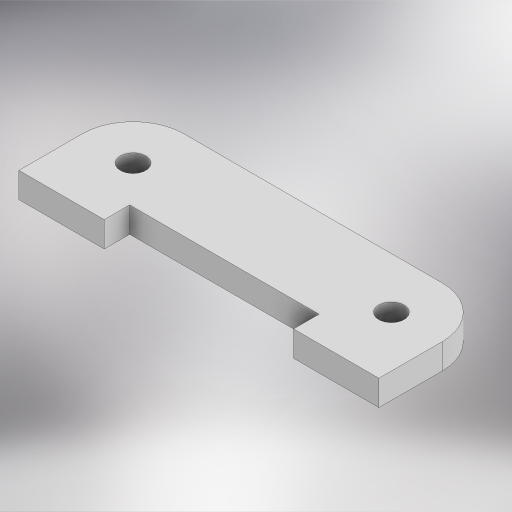
# Autodesk Inventor part: board_holder
Saved by Autodesk Inventor 2023.5 (Build 275446000, 446)
## iProperties
Created: 2026-10-31
Part Number: board_holder
Material: Generic
Document SubType Name: Modeling
Designer: WORKPLUS
Density: 1 g/cm^3
Appearance: Default
Author: WORKPLUS
Autodesk Inventor part; units mm, degrees
ref_plane "YZ Plane" through (0, 0, 0) normal (1, 0, 0) x (0, 1, 0)
ref_plane "XZ Plane" through (0, 0, 0) normal (0, 1, 0) x (-1, 0, 0)
ref_plane "XY Plane" through (0, 0, 0) normal (0, 0, 1) x (1, 0, 0)
sketch "Sketch1" plane through (0, 0, 0) normal (0, 1, 0) x (-1, 0, 0)
  line L0 (35.4, -23.719) -> (35.4, -36.169)
  line L1 (25.4, -46.169) -> (-25.4, -46.169)
  line L2 (-35.4, -36.169) -> (-35.4, -23.719)
  circle A0 centre (25.4, -36.169) radius 2.5
  circle A1 centre (-25.4, -36.169) radius 2.5
  arc A2 (25.4, -46.169) -> (35.4, -36.169) centre (25.4, -36.169) ccw
  arc A3 (-35.4, -36.169) -> (-25.4, -46.169) centre (-25.4, -36.169) ccw
  line L3 (-18.6144, -21.219) -> (-18.6146, -21.219)
  line L4 (-18.6146, -23.719) -> (-18.6146, -28.719)
  line L5 (-18.6146, -28.719) -> (18.6144, -28.719)
  line L6 (18.6144, -28.719) -> (18.6144, -23.719)
  line L7 (18.6144, -28.719) -> (-18.6146, -28.719)
  line L8 (-35.4, -28.719) -> (-35.4, -23.719)
  line L9 (35.4, -23.719) -> (35.4, -28.719)
  line L10 (-35.4, -23.719) -> (-18.6146, -23.719)
  line L11 (18.6144, -23.719) -> (35.4, -23.719)
  point P0 (0, 0)
  dimension "d1" = 5
  dimension "d2" = 5
  dimension "d3" = 25.4
  dimension "d4" = 25.4
  dimension "d5" = 10
  dimension "d6" = 10
  dimension "d8" = 10
  dimension "d9" = 10
  dimension "d12" = 10
  dimension "d16" = 37.229
  dimension "d17" = 7.5
  constraints: 24 end point, 6 parallel, 4 centre point, 4 point on circle, 4 tangent, 2 horizontal, 2 perpendicular, 1 point on line
  measures "d1" diameter of A0
  measures "d2" diameter of A1
  measures "d3" horizontal distance of point (0, 0) A1.centre
  measures "d4" horizontal distance of point (0, 0) A0.centre
  measures "d5" distance from line of L1 A0.centre
  measures "d6" distance from line of L0 A0.centre
  measures "d8" radius of A2
  measures "d9" radius of A3
  measures "d12" distance from line of L1 A1.centre
  measures "d16" distance of L5.end L4.end
  measures "d17" distance of L4.end L3.end
extrude "Extrusion1" add sketch "Sketch1" along normal blind 5
body "Solid1"
